ScanParts - Scanner v5 (Autodesk Fusion 360 design; units mm, degrees)
part number: 2026-11-14-11-23-10-393
part number: 2026-11-14-11-23-14-018
part number: 2026-11-14-11-23-14-713
part number: 2026-11-14-11-23-15-283
part number: 2026-11-14-11-23-16-065
part number: 2026-11-14-11-23-16-734
part number: 2026-11-14-11-23-24-762
part number: 2026-11-14-11-23-25-385
part number: 2026-11-14-11-23-25-910
part number: 2026-11-14-11-23-26-535
part number: 2026-11-14-11-23-27-518
part number: 2026-11-14-11-23-28-138
part number: 2026-11-14-11-23-28-822
part number: 2026-11-14-11-23-29-557
part number: 2026-11-14-11-23-30-858
part number: 2026-11-14-11-23-31-655
part number: 2026-11-14-11-23-33-125
part number: 2026-11-14-11-23-34-058
part number: 2026-11-14-11-24-18-527
part number: 2026-11-14-11-24-22-530
part number: 2026-11-14-11-24-37-352
part number: 2026-11-14-11-24-41-219
Autodesk Fusion 360 part; units mm, degrees
sketch "Esboço1" plane through (0, 0, 0) normal (0, 0, 1) x (1, 0, 0) in component "Pé de borracha Ø20×30"
  circle A0 centre (0, 0) radius 10
extrude "Extrusão1" add sketch "Esboço1" along normal blind 30 makes body 1 in component "Pé de borracha Ø20×30"
ref_plane "Plano de trabalho1" through (0, 0, 30) normal (0, 0, 1) x (1, 0, 0) in component "Base MDF"
sketch "Esboço1 (2)" plane through (0, 0, 30) normal (0, 0, 1) x (1, 0, 0) in component "Base MDF"
  line L0 (-130, -120) -> (130, -120)
  line L1 (130, -120) -> (130, 150)
  line L2 (130, 150) -> (-130, 150)
  line L3 (-130, 150) -> (-130, -120)
  circle A0 centre (0, 0) radius 6
extrude "Extrusão1'" add sketch "Esboço1 (2)" along normal blind 15 separate body makes body 2 in component "Base MDF"
ref_plane "Plano de trabalho2" through (0, 0, 30) normal (0, 0, 1) x (1, 0, 0) in component "Base MDF"
sketch "Esboço2" plane through (0, 0, 30) normal (0, 0, 1) x (1, 0, 0) in component "Base MDF"
  line L0 (-10.2, 94.8) -> (10.2, 94.8)
  line L1 (10.2, 94.8) -> (10.2, 115.2)
  line L2 (10.2, 115.2) -> (-10.2, 115.2)
  line L3 (-10.2, 115.2) -> (-10.2, 94.8)
extrude "Extrusão2" cut sketch "Esboço2" along normal blind 15 bodies 2 in component "Base MDF"
ref_plane "Plano de trabalho1" through (0, 0, 11) normal (0, 0, 1) x (1, 0, 0) in component "Motor de passo 28BYJ-48"
sketch "Esboço1 (3)" plane through (0, 0, 11) normal (0, 0, 1) x (1, 0, 0) in component "Motor de passo 28BYJ-48"
  circle A0 centre (0, -8) radius 14
extrude "Extrusão1''" add sketch "Esboço1 (3)" along normal blind 19 separate body makes body 3 in component "Motor de passo 28BYJ-48"
ref_plane "Plano de trabalho2" through (0, 0, 29) normal (0, 0, 1) x (1, 0, 0) in component "Motor de passo 28BYJ-48"
sketch "Esboço2 (2)" plane through (0, 0, 29) normal (0, 0, 1) x (1, 0, 0) in component "Motor de passo 28BYJ-48"
  line L0 (-3.5, -29) -> (3.5, -29)
  line L1 (3.5, -29) -> (3.5, 13)
  line L2 (3.5, 13) -> (-3.5, 13)
  line L3 (-3.5, 13) -> (-3.5, -29)
  circle A0 centre (0, -25.5) radius 2.1
  circle A1 centre (0, 9.5) radius 2.1
extrude "Extrusão2'" add sketch "Esboço2 (2)" along normal blind 1 separate body makes body 4 in component "Motor de passo 28BYJ-48"
ref_plane "Plano de trabalho3" through (0, 0, 30) normal (0, 0, 1) x (1, 0, 0) in component "Motor de passo 28BYJ-48"
sketch "Esboço3" plane through (0, 0, 30) normal (0, 0, 1) x (1, 0, 0) in component "Motor de passo 28BYJ-48"
  circle A0 centre (0, 0) radius 2.5
extrude "Extrusão3" add sketch "Esboço3" along normal blind 19 separate body makes body 5 in component "Motor de passo 28BYJ-48"
ref_plane "Plano de trabalho1" through (0, 0, 47) normal (0, 0, 1) x (1, 0, 0) in component "Prato giratório Ø180"
sketch "Esboço1 (4)" plane through (0, 0, 47) normal (0, 0, 1) x (1, 0, 0) in component "Prato giratório Ø180"
  circle A0 centre (0, 0) radius 90
extrude "Extrusão1'''" add sketch "Esboço1 (4)" along normal blind 4 separate body makes body 6 in component "Prato giratório Ø180"
ref_plane "Plano de trabalho2" through (0, 0, 47) normal (0, 0, 1) x (1, 0, 0) in component "Prato giratório Ø180"
sketch "Esboço2 (3)" plane through (0, 0, 47) normal (0, 0, 1) x (1, 0, 0) in component "Prato giratório Ø180"
  circle A0 centre (0, 0) radius 2.5
extrude "Extrusão4" cut sketch "Esboço2 (3)" along normal blind 2 bodies 5 in component "Motor de passo 28BYJ-48"
extrude "Extrusão2''" cut sketch "Esboço2 (3)" along normal blind 2 bodies 6 in component "Prato giratório Ø180"
ref_plane "Plano de trabalho1" through (0, 0, 51) normal (0, 0, 1) x (1, 0, 0) in component "Alvos de referência (24× a cada 15°)"
sketch "Esboço1 (5)" plane through (0, 0, 51) normal (0, 0, 1) x (1, 0, 0) in component "Alvos de referência (24× a cada 15°)"
  line L0 (76.5, -3.5) -> (83.5, -3.5)
  line L1 (83.5, -3.5) -> (83.5, 3.5)
  line L2 (83.5, 3.5) -> (76.5, 3.5)
  line L3 (76.5, 3.5) -> (76.5, -3.5)
  line L4 (74.7992, 16.4189) -> (81.5607, 18.2306)
  line L5 (81.5607, 18.2306) -> (79.7489, 24.9921)
  line L6 (79.7489, 24.9921) -> (72.9875, 23.1804)
  line L7 (72.9875, 23.1804) -> (74.7992, 16.4189)
  line L8 (68.0009, 35.2189) -> (74.0631, 38.7189)
  line L9 (74.0631, 38.7189) -> (70.5631, 44.7811)
  line L10 (70.5631, 44.7811) -> (64.5009, 41.2811)
  line L11 (64.5009, 41.2811) -> (68.0009, 35.2189)
  line L12 (56.5685, 51.6188) -> (61.5183, 56.5685)
  line L13 (61.5183, 56.5685) -> (56.5685, 61.5183)
  line L14 (56.5685, 61.5183) -> (51.6188, 56.5685)
  line L15 (51.6188, 56.5685) -> (56.5685, 51.6188)
  line L16 (41.2811, 64.5009) -> (44.7811, 70.5631)
  line L17 (44.7811, 70.5631) -> (38.7189, 74.0631)
  line L18 (38.7189, 74.0631) -> (35.2189, 68.0009)
  line L19 (35.2189, 68.0009) -> (41.2811, 64.5009)
  line L20 (23.1804, 72.9875) -> (24.9921, 79.7489)
  line L21 (24.9921, 79.7489) -> (18.2306, 81.5607)
  line L22 (18.2306, 81.5607) -> (16.4189, 74.7992)
  line L23 (16.4189, 74.7992) -> (23.1804, 72.9875)
  line L24 (3.5, 76.5) -> (3.5, 83.5)
  line L25 (3.5, 83.5) -> (-3.5, 83.5)
  line L26 (-3.5, 83.5) -> (-3.5, 76.5)
  line L27 (-3.5, 76.5) -> (3.5, 76.5)
  line L28 (-16.4189, 74.7992) -> (-18.2306, 81.5607)
  line L29 (-18.2306, 81.5607) -> (-24.9921, 79.7489)
  line L30 (-24.9921, 79.7489) -> (-23.1804, 72.9875)
  line L31 (-23.1804, 72.9875) -> (-16.4189, 74.7992)
  line L32 (-35.2189, 68.0009) -> (-38.7189, 74.0631)
  line L33 (-38.7189, 74.0631) -> (-44.7811, 70.5631)
  line L34 (-44.7811, 70.5631) -> (-41.2811, 64.5009)
  line L35 (-41.2811, 64.5009) -> (-35.2189, 68.0009)
  line L36 (-51.6188, 56.5685) -> (-56.5685, 61.5183)
  line L37 (-56.5685, 61.5183) -> (-61.5183, 56.5685)
  line L38 (-61.5183, 56.5685) -> (-56.5685, 51.6188)
  line L39 (-56.5685, 51.6188) -> (-51.6188, 56.5685)
  line L40 (-64.5009, 41.2811) -> (-70.5631, 44.7811)
  line L41 (-70.5631, 44.7811) -> (-74.0631, 38.7189)
  line L42 (-74.0631, 38.7189) -> (-68.0009, 35.2189)
  line L43 (-68.0009, 35.2189) -> (-64.5009, 41.2811)
  line L44 (-72.9875, 23.1804) -> (-79.7489, 24.9921)
  line L45 (-79.7489, 24.9921) -> (-81.5607, 18.2306)
  line L46 (-81.5607, 18.2306) -> (-74.7992, 16.4189)
  line L47 (-74.7992, 16.4189) -> (-72.9875, 23.1804)
  line L48 (-76.5, 3.5) -> (-83.5, 3.5)
  line L49 (-83.5, 3.5) -> (-83.5, -3.5)
  line L50 (-83.5, -3.5) -> (-76.5, -3.5)
  line L51 (-76.5, -3.5) -> (-76.5, 3.5)
  line L52 (-74.7992, -16.4189) -> (-81.5607, -18.2306)
  line L53 (-81.5607, -18.2306) -> (-79.7489, -24.9921)
  line L54 (-79.7489, -24.9921) -> (-72.9875, -23.1804)
  line L55 (-72.9875, -23.1804) -> (-74.7992, -16.4189)
  line L56 (-68.0009, -35.2189) -> (-74.0631, -38.7189)
  line L57 (-74.0631, -38.7189) -> (-70.5631, -44.7811)
  line L58 (-70.5631, -44.7811) -> (-64.5009, -41.2811)
  line L59 (-64.5009, -41.2811) -> (-68.0009, -35.2189)
  line L60 (-56.5685, -51.6188) -> (-61.5183, -56.5685)
  line L61 (-61.5183, -56.5685) -> (-56.5685, -61.5183)
  line L62 (-56.5685, -61.5183) -> (-51.6188, -56.5685)
  line L63 (-51.6188, -56.5685) -> (-56.5685, -51.6188)
  line L64 (-41.2811, -64.5009) -> (-44.7811, -70.5631)
  line L65 (-44.7811, -70.5631) -> (-38.7189, -74.0631)
  line L66 (-38.7189, -74.0631) -> (-35.2189, -68.0009)
  line L67 (-35.2189, -68.0009) -> (-41.2811, -64.5009)
  line L68 (-23.1804, -72.9875) -> (-24.9921, -79.7489)
  line L69 (-24.9921, -79.7489) -> (-18.2306, -81.5607)
  line L70 (-18.2306, -81.5607) -> (-16.4189, -74.7992)
  line L71 (-16.4189, -74.7992) -> (-23.1804, -72.9875)
  line L72 (-3.5, -76.5) -> (-3.5, -83.5)
  line L73 (-3.5, -83.5) -> (3.5, -83.5)
  line L74 (3.5, -83.5) -> (3.5, -76.5)
  line L75 (3.5, -76.5) -> (-3.5, -76.5)
  line L76 (16.4189, -74.7992) -> (18.2306, -81.5607)
  line L77 (18.2306, -81.5607) -> (24.9921, -79.7489)
  line L78 (24.9921, -79.7489) -> (23.1804, -72.9875)
  line L79 (23.1804, -72.9875) -> (16.4189, -74.7992)
  line L80 (35.2189, -68.0009) -> (38.7189, -74.0631)
  line L81 (38.7189, -74.0631) -> (44.7811, -70.5631)
  line L82 (44.7811, -70.5631) -> (41.2811, -64.5009)
  line L83 (41.2811, -64.5009) -> (35.2189, -68.0009)
  line L84 (51.6188, -56.5685) -> (56.5685, -61.5183)
  line L85 (56.5685, -61.5183) -> (61.5183, -56.5685)
  line L86 (61.5183, -56.5685) -> (56.5685, -51.6188)
  line L87 (56.5685, -51.6188) -> (51.6188, -56.5685)
  line L88 (64.5009, -41.2811) -> (70.5631, -44.7811)
  line L89 (70.5631, -44.7811) -> (74.0631, -38.7189)
  line L90 (74.0631, -38.7189) -> (68.0009, -35.2189)
  line L91 (68.0009, -35.2189) -> (64.5009, -41.2811)
  line L92 (72.9875, -23.1804) -> (79.7489, -24.9921)
  line L93 (79.7489, -24.9921) -> (81.5607, -18.2306)
  line L94 (81.5607, -18.2306) -> (74.7992, -16.4189)
  line L95 (74.7992, -16.4189) -> (72.9875, -23.1804)
extrude "Extrusão1''''" add sketch "Esboço1 (5)" along normal blind 0.3 separate body makes body 7 at (68.855, -38.4063, 51) makes body 8 at (41.5937, -69.7091, 51) makes body 9 at (-1.1667, -81.1667, 51) makes body 10 at (-40.427, -67.6883, 51) makes body 11 at (-69.7091, -41.5937, 51) makes body 12 at (-81.1667, 1.1667, 51) makes body 13 at (-78.099, 22.1344, 51) makes body 14 at (-58.2185, 56.5685, 51) makes body 15 at (-19.2767, 76.4491, 51) makes body 16 at (19.2767, 76.4491, 51) makes body 17 at (56.5685, 54.9186, 51) makes body 18 at (76.4491, 19.2767, 51) makes body 19 at (68.855, 38.4063, 51) makes body 20 at (40.427, 67.6883, 51) makes body 21 at (1.1667, 78.8333, 51) makes body 22 at (-38.4063, 68.855, 51) makes body 23 at (-69.7091, 41.5937, 51) makes body 24 at (78.8333, 1.1667, 51) makes body 25 at (-78.099, -22.1344, 51) makes body 26 at (-56.5685, -58.2185, 51) makes body 27 at (-22.1344, -78.099, 51) makes body 28 at (22.1344, -78.099, 51) makes body 29 at (54.9186, -56.5685, 51) makes body 30 at (78.099, -22.1344, 51) in component "Alvos de referência (24× a cada 15°)"
ref_plane "Plano de trabalho1" through (0, 0, 22) normal (0, 0, 1) x (1, 0, 0) in component "Flange da haste (sob a base)"
sketch "Esboço1 (6)" plane through (0, 0, 22) normal (0, 0, 1) x (1, 0, 0) in component "Flange da haste (sob a base)"
  line L0 (-25, 80) -> (25, 80)
  line L1 (25, 80) -> (25, 130)
  line L2 (25, 130) -> (-25, 130)
  line L3 (-25, 130) -> (-25, 80)
  circle A0 centre (-17, 88) radius 2.5
  circle A1 centre (-17, 122) radius 2.5
  circle A2 centre (17, 88) radius 2.5
  circle A3 centre (17, 122) radius 2.5
extrude "Extrusão1'''''" add sketch "Esboço1 (6)" along normal blind 8 separate body makes body 31 in component "Flange da haste (sob a base)"
ref_plane "Plano de trabalho1" through (0, 0, 30) normal (0, 0, 1) x (1, 0, 0) in component "Haste vertical 20x20 (175 mm)"
sketch "Esboço1 (7)" plane through (0, 0, 30) normal (0, 0, 1) x (1, 0, 0) in component "Haste vertical 20x20 (175 mm)"
  line L0 (-10, 95) -> (10, 95)
  line L1 (10, 95) -> (10, 115)
  line L2 (10, 115) -> (-10, 115)
  line L3 (-10, 115) -> (-10, 95)
  circle A0 centre (0, 105) radius 2.1
extrude "Extrusão1''''''" add sketch "Esboço1 (7)" along normal blind 175 separate body makes body 32 in component "Haste vertical 20x20 (175 mm)"
ref_plane "Plano de trabalho1" through (0, 0, 159) normal (0, 0, 1) x (1, 0, 0) in component "Carro de ajuste"
sketch "Esboço1 (8)" plane through (0, 0, 159) normal (0, 0, 1) x (1, 0, 0) in component "Carro de ajuste"
  line L0 (-20, 85) -> (20, 85)
  line L1 (20, 85) -> (20, 125)
  line L2 (20, 125) -> (-20, 125)
  line L3 (-20, 125) -> (-20, 85)
  line L4 (-10.2, 94.8) -> (10.2, 94.8)
  line L5 (10.2, 94.8) -> (10.2, 115.2)
  line L6 (10.2, 115.2) -> (-10.2, 115.2)
  line L7 (-10.2, 115.2) -> (-10.2, 94.8)
extrude "Extrusão1'''''''" add sketch "Esboço1 (8)" along normal blind 40 separate body makes body 33 in component "Carro de ajuste"
ref_plane "Plano de trabalho1" through (20, 0, 0) normal (1, 0, 0) x (0, 1, 0) in component "Manípulo"
sketch "Esboço1 (9)" plane through (20, 0, 0) normal (1, 0, 0) x (0, 0, -1) in component "Manípulo"
  circle A0 centre (-179, 105) radius 4
extrude "Extrusão1''''''''" add sketch "Esboço1 (9)" along normal blind 10 separate body makes body 34 in component "Manípulo"
ref_plane "Plano de trabalho2" through (30, 0, 0) normal (1, 0, 0) x (0, 1, 0) in component "Manípulo"
sketch "Esboço2 (4)" plane through (30, 0, 0) normal (1, 0, 0) x (0, 0, -1) in component "Manípulo"
  circle A0 centre (-179, 105) radius 11
extrude "Extrusão2'''" add sketch "Esboço2 (4)" along normal blind 8 separate body makes body 35 in component "Manípulo"
ref_plane "Plano de trabalho1" through (0, 0, 169) normal (0, 0, 1) x (1, 0, 0) in component "Braço 20x20 (55 mm)"
sketch "Esboço1 (10)" plane through (0, 0, 169) normal (0, 0, 1) x (1, 0, 0) in component "Braço 20x20 (55 mm)"
  line L0 (-10, 30) -> (10, 30)
  line L1 (10, 30) -> (10, 85)
  line L2 (10, 85) -> (-10, 85)
  line L3 (-10, 85) -> (-10, 30)
extrude "Extrusão1'''''''''" add sketch "Esboço1 (10)" along normal blind 20 separate body makes body 36 in component "Braço 20x20 (55 mm)"
ref_plane "Plano de trabalho1" through (0, 0, 164) normal (0, 0, 1) x (1, 0, 0) in component "Suporte câmera + LED Ø170"
sketch "Esboço1 (11)" plane through (0, 0, 164) normal (0, 0, 1) x (1, 0, 0) in component "Suporte câmera + LED Ø170"
  circle A0 centre (0, 0) radius 85
  circle A1 centre (0, 0) radius 8
extrude "Extrusão1''''''''''" add sketch "Esboço1 (11)" along normal blind 5 separate body makes body 37 in component "Suporte câmera + LED Ø170"
ref_plane "Plano de trabalho1" through (0, 0, 152) normal (0, 0, 1) x (1, 0, 0) in component "Ring light 6500K Ø160"
sketch "Esboço1 (12)" plane through (0, 0, 152) normal (0, 0, 1) x (1, 0, 0) in component "Ring light 6500K Ø160"
  circle A0 centre (0, 0) radius 80
  circle A1 centre (0, 0) radius 55
extrude "Extrusão1'''''''''''" add sketch "Esboço1 (12)" along normal blind 12 separate body makes body 38 in component "Ring light 6500K Ø160"
ref_plane "Plano de trabalho1" through (0, 0, 169) normal (0, 0, 1) x (1, 0, 0) in component "Câmera IMX219"
sketch "Esboço1 (13)" plane through (0, 0, 169) normal (0, 0, 1) x (1, 0, 0) in component "Câmera IMX219"
  line L0 (-12.5, -12) -> (12.5, -12)
  line L1 (12.5, -12) -> (12.5, 12)
  line L2 (12.5, 12) -> (-12.5, 12)
  line L3 (-12.5, 12) -> (-12.5, -12)
extrude "Extrusão1''''''''''''" add sketch "Esboço1 (13)" along normal blind 1.6 separate body makes body 39 in component "Câmera IMX219"
ref_plane "Plano de trabalho2" through (0, 0, 151) normal (0, 0, 1) x (1, 0, 0) in component "Câmera IMX219"
sketch "Esboço2 (5)" plane through (0, 0, 151) normal (0, 0, 1) x (1, 0, 0) in component "Câmera IMX219"
  circle A0 centre (0, 0) radius 7
extrude "Extrusão2''''" add sketch "Esboço2 (5)" along normal blind 18 separate body makes body 40 in component "Câmera IMX219"
ref_plane "Plano de trabalho1" through (0, 0, 148) normal (0, 0, 1) x (1, 0, 0) in component "Filtro polarizador CPL"
sketch "Esboço1 (14)" plane through (0, 0, 148) normal (0, 0, 1) x (1, 0, 0) in component "Filtro polarizador CPL"
  circle A0 centre (0, 0) radius 8
  circle A1 centre (0, 0) radius 5
extrude "Extrusão1'''''''''''''" add sketch "Esboço1 (14)" along normal blind 3 separate body makes body 41 in component "Filtro polarizador CPL"
ref_plane "Plano de trabalho1" through (0, 0, 169) normal (0, 0, 1) x (1, 0, 0) in component "Suporte do laser"
sketch "Esboço1 (15)" plane through (0, 0, 169) normal (0, 0, 1) x (1, 0, 0) in component "Suporte do laser"
  line L0 (10, -110) -> (16, -110)
  line L1 (16, -110) -> (16, -75)
  line L2 (16, -75) -> (10, -75)
  line L3 (10, -75) -> (10, -110)
extrude "Extrusão1''''''''''''''" add sketch "Esboço1 (15)" along normal blind 3 separate body makes body 42 in component "Suporte do laser"
ref_plane "Plano de trabalho2" through (0, 0, 138) normal (0, 0, 1) x (1, 0, 0) in component "Suporte do laser"
sketch "Esboço2 (6)" plane through (0, 0, 138) normal (0, 0, 1) x (1, 0, 0) in component "Suporte do laser"
  line L0 (10, -110) -> (16, -110)
  line L1 (16, -110) -> (16, -92)
  line L2 (16, -92) -> (10, -92)
  line L3 (10, -92) -> (10, -110)
extrude "Extrusão2'''''" add sketch "Esboço2 (6)" along normal blind 31 separate body makes body 43 in component "Suporte do laser"
ref_plane "Plano de trabalho1" through (0, 0, -7) normal (0, 0, 1) x (1, 0, 0) in component "Abraçadeira do laser"
sketch "Esboço1 (16)" plane through (0, 0, -7) normal (0, 0, 1) x (1, 0, 0) in component "Abraçadeira do laser"
  circle A0 centre (0, 0) radius 10
  circle A1 centre (0, 0) radius 6
extrude "Extrusão1'''''''''''''''" add sketch "Esboço1 (16)" along normal blind 14 separate body makes body 44 in component "Abraçadeira do laser"
ref_plane "Plano de trabalho1" through (0, 0, -15) normal (0, 0, 1) x (1, 0, 0) in component "Laser de linha 650 nm Ø12"
sketch "Esboço1 (17)" plane through (0, 0, -15) normal (0, 0, 1) x (1, 0, 0) in component "Laser de linha 650 nm Ø12"
  circle A0 centre (0, 0) radius 6
extrude "Extrusão1''''''''''''''''" add sketch "Esboço1 (17)" along normal blind 30 separate body makes body 45 in component "Laser de linha 650 nm Ø12"
ref_plane "Plano de trabalho2" through (0, 0, -16) normal (0, 0, 1) x (1, 0, 0) in component "Laser de linha 650 nm Ø12"
sketch "Esboço2 (7)" plane through (0, 0, -16) normal (0, 0, 1) x (1, 0, 0) in component "Laser de linha 650 nm Ø12"
  circle A0 centre (0, 0) radius 3
extrude "Extrusão2''''''" add sketch "Esboço2 (7)" along normal blind 1 separate body makes body 46 in component "Laser de linha 650 nm Ø12"
ref_plane "Plano de trabalho1" through (0, 0, 196) normal (0, 0, 1) x (1, 0, 0) in component "Plataforma do Jetson"
sketch "Esboço1 (18)" plane through (0, 0, 196) normal (0, 0, 1) x (1, 0, 0) in component "Plataforma do Jetson"
  line L0 (-58, -8) -> (37, -8)
  line L1 (37, -8) -> (37, 83)
  line L2 (37, 83) -> (-58, 83)
  line L3 (-58, 83) -> (-58, -8)
extrude "Extrusão1'''''''''''''''''" add sketch "Esboço1 (18)" along normal blind 4 separate body makes body 47 in component "Plataforma do Jetson"
ref_plane "Plano de trabalho2" through (0, 0, 189) normal (0, 0, 1) x (1, 0, 0) in component "Plataforma do Jetson"
sketch "Esboço2 (8)" plane through (0, 0, 189) normal (0, 0, 1) x (1, 0, 0) in component "Plataforma do Jetson"
  line L0 (-10, 45) -> (10, 45)
  line L1 (10, 45) -> (10, 57)
  line L2 (10, 57) -> (-10, 57)
  line L3 (-10, 57) -> (-10, 45)
extrude "Extrusão2'''''''" add sketch "Esboço2 (8)" along normal blind 7 separate body makes body 48 in component "Plataforma do Jetson"
ref_plane "Plano de trabalho3" through (0, 0, 189) normal (0, 0, 1) x (1, 0, 0) in component "Plataforma do Jetson"
sketch "Esboço3 (2)" plane through (0, 0, 189) normal (0, 0, 1) x (1, 0, 0) in component "Plataforma do Jetson"
  line L0 (-10, 70) -> (10, 70)
  line L1 (10, 70) -> (10, 82)
  line L2 (10, 82) -> (-10, 82)
  line L3 (-10, 82) -> (-10, 70)
extrude "Extrusão3'" add sketch "Esboço3 (2)" along normal blind 7 separate body makes body 49 in component "Plataforma do Jetson"
ref_plane "Plano de trabalho4" through (0, 0, 169) normal (0, 0, 1) x (1, 0, 0) in component "Plataforma do Jetson"
sketch "Esboço4" plane through (0, 0, 169) normal (0, 0, 1) x (1, 0, 0) in component "Plataforma do Jetson"
  circle A0 centre (-45, 5) radius 4
extrude "Extrusão4'" add sketch "Esboço4" along normal blind 27 separate body makes body 50 in component "Plataforma do Jetson"
ref_plane "Plano de trabalho5" through (0, 0, 169) normal (0, 0, 1) x (1, 0, 0) in component "Plataforma do Jetson"
sketch "Esboço5" plane through (0, 0, 169) normal (0, 0, 1) x (1, 0, 0) in component "Plataforma do Jetson"
  circle A0 centre (28, 5) radius 4
extrude "Extrusão5" add sketch "Esboço5" along normal blind 27 separate body makes body 51 in component "Plataforma do Jetson"
sketch "Esboço1 (19)" plane through (0, 0, 0) normal (0, 0, 1) x (1, 0, 0) in component "Jetson Orin Nano Dev Kit"
  line L0 (0, 0) -> (103, 0)
  line L1 (103, 0) -> (103, 90.5)
  line L2 (103, 90.5) -> (0, 90.5)
  line L3 (0, 90.5) -> (0, 0)
extrude "Extrusão1''''''''''''''''''" add sketch "Esboço1 (19)" along normal blind 6 separate body makes body 52 in component "Jetson Orin Nano Dev Kit"
ref_plane "Plano de trabalho1" through (0, 0, 6) normal (0, 0, 1) x (1, 0, 0) in component "Jetson Orin Nano Dev Kit"
sketch "Esboço2 (9)" plane through (0, 0, 6) normal (0, 0, 1) x (1, 0, 0) in component "Jetson Orin Nano Dev Kit"
  line L0 (1.5, 2) -> (101.5, 2)
  line L1 (101.5, 2) -> (101.5, 81)
  line L2 (101.5, 81) -> (1.5, 81)
  line L3 (1.5, 81) -> (1.5, 2)
  circle A0 centre (5.3, 77) radius 1.35
  circle A1 centre (96.8, 77) radius 1.35
  circle A2 centre (5.3, 18.3) radius 1.35
  circle A3 centre (96.8, 18.3) radius 1.35
extrude "Extrusão2''''''''" add sketch "Esboço2 (9)" along normal blind 1.57 separate body makes body 53 in component "Jetson Orin Nano Dev Kit"
ref_plane "Plano de trabalho2" through (0, 0, 10.97) normal (0, 0, 1) x (1, 0, 0) in component "Jetson Orin Nano Dev Kit"
sketch "Esboço3 (3)" plane through (0, 0, 10.97) normal (0, 0, 1) x (1, 0, 0) in component "Jetson Orin Nano Dev Kit"
  line L0 (15, 36) -> (84.6, 36)
  line L1 (84.6, 36) -> (84.6, 81)
  line L2 (84.6, 81) -> (15, 81)
  line L3 (15, 81) -> (15, 36)
extrude "Extrusão3''" add sketch "Esboço3 (3)" along normal blind 1 separate body makes body 54 in component "Jetson Orin Nano Dev Kit"
ref_plane "Plano de trabalho3" through (0, 0, 11.97) normal (0, 0, 1) x (1, 0, 0) in component "Jetson Orin Nano Dev Kit"
sketch "Esboço4 (2)" plane through (0, 0, 11.97) normal (0, 0, 1) x (1, 0, 0) in component "Jetson Orin Nano Dev Kit"
  line L0 (20.5, 40.9) -> (79, 40.9)
  line L1 (79, 40.9) -> (79, 80.2)
  line L2 (79, 80.2) -> (20.5, 80.2)
  line L3 (20.5, 80.2) -> (20.5, 40.9)
extrude "Extrusão4''" add sketch "Esboço4 (2)" along normal blind 22.8 separate body makes body 55 in component "Jetson Orin Nano Dev Kit"
ref_plane "Plano de trabalho4" through (0, 0, 34.77) normal (0, 0, 1) x (1, 0, 0) in component "Jetson Orin Nano Dev Kit"
sketch "Esboço5 (2)" plane through (0, 0, 34.77) normal (0, 0, 1) x (1, 0, 0) in component "Jetson Orin Nano Dev Kit"
  circle A0 centre (49.4, 60.6) radius 18
extrude "Extrusão5'" cut sketch "Esboço5 (2)" against normal blind 2 bodies 55 in component "Jetson Orin Nano Dev Kit"
ref_plane "Plano de trabalho5" through (0, 0, 32.77) normal (0, 0, 1) x (1, 0, 0) in component "Jetson Orin Nano Dev Kit"
sketch "Esboço6" plane through (0, 0, 32.77) normal (0, 0, 1) x (1, 0, 0) in component "Jetson Orin Nano Dev Kit"
  circle A0 centre (49.4, 60.6) radius 7
extrude "Extrusão6" add sketch "Esboço6" along normal blind 2 separate body makes body 56 in component "Jetson Orin Nano Dev Kit"
ref_plane "Plano de trabalho6" through (0, 0, 7.57) normal (0, 0, 1) x (1, 0, 0) in component "Jetson Orin Nano Dev Kit"
sketch "Esboço7" plane through (0, 0, 7.57) normal (0, 0, 1) x (1, 0, 0) in component "Jetson Orin Nano Dev Kit"
  line L0 (2.7, 0) -> (12, 0)
  line L1 (12, 0) -> (12, 14)
  line L2 (12, 14) -> (2.7, 14)
  line L3 (2.7, 14) -> (2.7, 0)
extrude "Extrusão7" add sketch "Esboço7" along normal blind 11 separate body makes body 57 in component "Jetson Orin Nano Dev Kit"
ref_plane "Plano de trabalho7" through (0, 0, 7.57) normal (0, 0, 1) x (1, 0, 0) in component "Jetson Orin Nano Dev Kit"
sketch "Esboço8" plane through (0, 0, 7.57) normal (0, 0, 1) x (1, 0, 0) in component "Jetson Orin Nano Dev Kit"
  line L0 (15.2, 0) -> (32.6, 0)
  line L1 (32.6, 0) -> (32.6, 15)
  line L2 (32.6, 15) -> (15.2, 15)
  line L3 (15.2, 15) -> (15.2, 0)
extrude "Extrusão8" add sketch "Esboço8" along normal blind 8.5 separate body makes body 58 in component "Jetson Orin Nano Dev Kit"
ref_plane "Plano de trabalho8" through (0, 0, 7.57) normal (0, 0, 1) x (1, 0, 0) in component "Jetson Orin Nano Dev Kit"
sketch "Esboço9" plane through (0, 0, 7.57) normal (0, 0, 1) x (1, 0, 0) in component "Jetson Orin Nano Dev Kit"
  line L0 (36.9, 0) -> (51.2, 0)
  line L1 (51.2, 0) -> (51.2, 17.5)
  line L2 (51.2, 17.5) -> (36.9, 17.5)
  line L3 (36.9, 17.5) -> (36.9, 0)
extrude "Extrusão9" add sketch "Esboço9" along normal blind 16.5 separate body makes body 59 in component "Jetson Orin Nano Dev Kit"
ref_plane "Plano de trabalho9" through (0, 0, 7.57) normal (0, 0, 1) x (1, 0, 0) in component "Jetson Orin Nano Dev Kit"
sketch "Esboço10" plane through (0, 0, 7.57) normal (0, 0, 1) x (1, 0, 0) in component "Jetson Orin Nano Dev Kit"
  line L0 (53.8, 0) -> (68.1, 0)
  line L1 (68.1, 0) -> (68.1, 17.5)
  line L2 (68.1, 17.5) -> (53.8, 17.5)
  line L3 (53.8, 17.5) -> (53.8, 0)
extrude "Extrusão10" add sketch "Esboço10" along normal blind 16.5 separate body makes body 60 in component "Jetson Orin Nano Dev Kit"
ref_plane "Plano de trabalho10" through (0, 0, 7.57) normal (0, 0, 1) x (1, 0, 0) in component "Jetson Orin Nano Dev Kit"
sketch "Esboço11" plane through (0, 0, 7.57) normal (0, 0, 1) x (1, 0, 0) in component "Jetson Orin Nano Dev Kit"
  line L0 (70.4, 0) -> (86.5, 0)
  line L1 (86.5, 0) -> (86.5, 21)
  line L2 (86.5, 21) -> (70.4, 21)
  line L3 (70.4, 21) -> (70.4, 0)
extrude "Extrusão11" add sketch "Esboço11" along normal blind 13.5 separate body makes body 61 in component "Jetson Orin Nano Dev Kit"
ref_plane "Plano de trabalho11" through (0, 0, 7.57) normal (0, 0, 1) x (1, 0, 0) in component "Jetson Orin Nano Dev Kit"
sketch "Esboço12" plane through (0, 0, 7.57) normal (0, 0, 1) x (1, 0, 0) in component "Jetson Orin Nano Dev Kit"
  line L0 (89, 0) -> (99.8, 0)
  line L1 (99.8, 0) -> (99.8, 7.5)
  line L2 (99.8, 7.5) -> (89, 7.5)
  line L3 (89, 7.5) -> (89, 0)
extrude "Extrusão12" add sketch "Esboço12" along normal blind 3.5 separate body makes body 62 in component "Jetson Orin Nano Dev Kit"
ref_plane "Plano de trabalho12" through (0, 0, 7.57) normal (0, 0, 1) x (1, 0, 0) in component "Jetson Orin Nano Dev Kit"
sketch "Esboço13" plane through (0, 0, 7.57) normal (0, 0, 1) x (1, 0, 0) in component "Jetson Orin Nano Dev Kit"
  line L0 (95.4, 22.2) -> (100.7, 22.2)
  line L1 (100.7, 22.2) -> (100.7, 73)
  line L2 (100.7, 73) -> (95.4, 73)
  line L3 (95.4, 73) -> (95.4, 22.2)
extrude "Extrusão13" add sketch "Esboço13" along normal blind 8.5 separate body makes body 63 in component "Jetson Orin Nano Dev Kit"
ref_plane "Plano de trabalho13" through (0, 0, 7.57) normal (0, 0, 1) x (1, 0, 0) in component "Jetson Orin Nano Dev Kit"
sketch "Esboço14" plane through (0, 0, 7.57) normal (0, 0, 1) x (1, 0, 0) in component "Jetson Orin Nano Dev Kit"
  line L0 (1.4, 51.6) -> (6.2, 51.6)
  line L1 (6.2, 51.6) -> (6.2, 68.6)
  line L2 (6.2, 68.6) -> (1.4, 68.6)
  line L3 (1.4, 68.6) -> (1.4, 51.6)
extrude "Extrusão14" add sketch "Esboço14" along normal blind 2.5 separate body makes body 64 in component "Jetson Orin Nano Dev Kit"
ref_plane "Plano de trabalho14" through (0, 0, 7.57) normal (0, 0, 1) x (1, 0, 0) in component "Jetson Orin Nano Dev Kit"
sketch "Esboço15" plane through (0, 0, 7.57) normal (0, 0, 1) x (1, 0, 0) in component "Jetson Orin Nano Dev Kit"
  line L0 (1.4, 26.7) -> (6.2, 26.7)
  line L1 (6.2, 26.7) -> (6.2, 42.7)
  line L2 (6.2, 42.7) -> (1.4, 42.7)
  line L3 (1.4, 42.7) -> (1.4, 26.7)
extrude "Extrusão15" add sketch "Esboço15" along normal blind 2.5 separate body makes body 65 in component "Jetson Orin Nano Dev Kit"
ref_plane "Plano de trabalho1" through (0, 0, 170.6) normal (0, 0, 1) x (1, 0, 0) in component "Cabo flat da câmera 22 vias"
sketch "Esboço1 (20)" plane through (0, 0, 170.6) normal (0, 0, 1) x (1, 0, 0) in component "Cabo flat da câmera 22 vias"
  line L0 (-6, -12.6) -> (6, -12.6)
  line L1 (6, -12.6) -> (6, -8)
  line L2 (6, -8) -> (-6, -8)
  line L3 (-6, -8) -> (-6, -12.6)
extrude "Extrusão1'''''''''''''''''''" add sketch "Esboço1 (20)" along normal blind 0.3 separate body makes body 66 in component "Cabo flat da câmera 22 vias"
ref_plane "Plano de trabalho2" through (0, 0, 170.6) normal (0, 0, 1) x (1, 0, 0) in component "Cabo flat da câmera 22 vias"
sketch "Esboço2 (10)" plane through (0, 0, 170.6) normal (0, 0, 1) x (1, 0, 0) in component "Cabo flat da câmera 22 vias"
  line L0 (-6, -12.6) -> (6, -12.6)
  line L1 (6, -12.6) -> (6, -12.3)
  line L2 (6, -12.3) -> (-6, -12.3)
  line L3 (-6, -12.3) -> (-6, -12.6)
extrude "Extrusão2'''''''''" add sketch "Esboço2 (10)" along normal blind 39.82 separate body makes body 67 in component "Cabo flat da câmera 22 vias"
ref_plane "Plano de trabalho3" through (0, 0, 210.12) normal (0, 0, 1) x (1, 0, 0) in component "Cabo flat da câmera 22 vias"
sketch "Esboço3 (4)" plane through (0, 0, 210.12) normal (0, 0, 1) x (1, 0, 0) in component "Cabo flat da câmera 22 vias"
  line L0 (-6, -12.6) -> (6, -12.6)
  line L1 (6, -12.6) -> (6, -7)
  line L2 (6, -7) -> (-6, -7)
  line L3 (-6, -7) -> (-6, -12.6)
extrude "Extrusão3'''" add sketch "Esboço3 (4)" along normal blind 0.3 separate body makes body 68 in component "Cabo flat da câmera 22 vias"
sketch "Esboço1 (21)" plane through (0, 0, 0) normal (0, 0, 1) x (1, 0, 0) in component "Driver ULN2003"
  circle A0 centre (3, 3) radius 2.5
extrude "Extrusão1''''''''''''''''''''" add sketch "Esboço1 (21)" along normal blind 3 separate body makes body 69 in component "Driver ULN2003"
sketch "Esboço2 (11)" plane through (0, 0, 0) normal (0, 0, 1) x (1, 0, 0) in component "Driver ULN2003"
  circle A0 centre (29, 3) radius 2.5
extrude "Extrusão2''''''''''" add sketch "Esboço2 (11)" along normal blind 3 separate body makes body 70 in component "Driver ULN2003"
sketch "Esboço3 (5)" plane through (0, 0, 0) normal (0, 0, 1) x (1, 0, 0) in component "Driver ULN2003"
  circle A0 centre (3, 32) radius 2.5
extrude "Extrusão3''''" add sketch "Esboço3 (5)" along normal blind 3 separate body makes body 71 in component "Driver ULN2003"
sketch "Esboço4 (3)" plane through (0, 0, 0) normal (0, 0, 1) x (1, 0, 0) in component "Driver ULN2003"
  circle A0 centre (29, 32) radius 2.5
extrude "Extrusão4'''" add sketch "Esboço4 (3)" along normal blind 3 separate body makes body 72 in component "Driver ULN2003"
ref_plane "Plano de trabalho1" through (0, 0, 3) normal (0, 0, 1) x (1, 0, 0) in component "Driver ULN2003"
sketch "Esboço5 (3)" plane through (0, 0, 3) normal (0, 0, 1) x (1, 0, 0) in component "Driver ULN2003"
  line L0 (0, 0) -> (32, 0)
  line L1 (32, 0) -> (32, 35)
  line L2 (32, 35) -> (0, 35)
  line L3 (0, 35) -> (0, 0)
extrude "Extrusão5''" add sketch "Esboço5 (3)" along normal blind 1.6 separate body makes body 73 in component "Driver ULN2003"
ref_plane "Plano de trabalho2" through (0, 0, 4.6) normal (0, 0, 1) x (1, 0, 0) in component "Driver ULN2003"
sketch "Esboço6 (2)" plane through (0, 0, 4.6) normal (0, 0, 1) x (1, 0, 0) in component "Driver ULN2003"
  line L0 (6, 8) -> (26, 8)
  line L1 (26, 8) -> (26, 15)
  line L2 (26, 15) -> (6, 15)
  line L3 (6, 15) -> (6, 8)
extrude "Extrusão6'" add sketch "Esboço6 (2)" along normal blind 4 separate body makes body 74 in component "Driver ULN2003"
ref_plane "Plano de trabalho3" through (0, 0, 4.6) normal (0, 0, 1) x (1, 0, 0) in component "Driver ULN2003"
sketch "Esboço7 (2)" plane through (0, 0, 4.6) normal (0, 0, 1) x (1, 0, 0) in component "Driver ULN2003"
  line L0 (9, 24) -> (23, 24)
  line L1 (23, 24) -> (23, 30)
  line L2 (23, 30) -> (9, 30)
  line L3 (9, 30) -> (9, 24)
extrude "Extrusão7'" add sketch "Esboço7 (2)" along normal blind 7 separate body makes body 75 in component "Driver ULN2003"
component "Pé de borracha Ø20×30" placed x (1, 0, 0) y (0, 1, 0) z (0, 0, 1) at (110, -100, 0)
component "Pé de borracha Ø20×30" placed x (1, 0, 0) y (0, 1, 0) z (0, 0, 1) at (-110, -100, 0)
component "Pé de borracha Ø20×30" placed x (1, 0, 0) y (0, 1, 0) z (0, 0, 1) at (110, 130, 0)
component "Pé de borracha Ø20×30" placed x (1, 0, 0) y (0, 1, 0) z (0, 0, 1) at (-110, 130, 0)
component "Base MDF" placed x (1, 0, 0) y (0, 1, 0) z (0, 0, 1) at (0, 0, 0)
component "Motor de passo 28BYJ-48" placed x (1, 0, 0) y (0, 1, 0) z (0, 0, 1) at (0, 0, 0)
component "Prato giratório Ø180" placed x (1, 0, 0) y (0, 1, 0) z (0, 0, 1) at (0, 0, 0)
component "Alvos de referência (24× a cada 15°)" placed x (1, 0, 0) y (0, 1, 0) z (0, 0, 1) at (0, 0, 0)
component "Flange da haste (sob a base)" placed x (1, 0, 0) y (0, 1, 0) z (0, 0, 1) at (0, 0, 0)
component "Haste vertical 20x20 (175 mm)" placed x (1, 0, 0) y (0, 1, 0) z (0, 0, 1) at (0, 0, 0)
component "Carro de ajuste" placed x (1, 0, 0) y (0, 1, 0) z (0, 0, 1) at (0, 0, 0)
component "Manípulo" placed x (1, 0, 0) y (0, 1, 0) z (0, 0, 1) at (0, 0, 0)
component "Braço 20x20 (55 mm)" placed x (1, 0, 0) y (0, 1, 0) z (0, 0, 1) at (0, 0, 0)
component "Suporte câmera + LED Ø170" placed x (1, 0, 0) y (0, 1, 0) z (0, 0, 1) at (0, 0, 0)
component "Ring light 6500K Ø160" placed x (1, 0, 0) y (0, 1, 0) z (0, 0, 1) at (0, 0, 0)
component "Câmera IMX219" placed x (1, 0, 0) y (0, 1, 0) z (0, 0, 1) at (0, 0, 0)
component "Filtro polarizador CPL" placed x (1, 0, 0) y (0, 1, 0) z (0, 0, 1) at (0, 0, 0)
component "Suporte do laser" placed x (1, 0, 0) y (0, 1, 0) z (0, 0, 1) at (0, 0, 0)
component "Abraçadeira do laser" placed x (1, 0, 0) y (0, 0.703545, 0.710651) z (0, -0.710651, 0.703545) at (0, -100, 150)
component "Laser de linha 650 nm Ø12" placed x (1, 0, 0) y (0, 0.703545, 0.710651) z (0, -0.710651, 0.703545) at (0, -100, 150)
component "Plataforma do Jetson" placed x (1, 0, 0) y (0, 1, 0) z (0, 0, 1) at (0, 0, 0)
component "Jetson Orin Nano Dev Kit" placed x (0, 1, 0) y (-1, 0, 0) z (0, 0, 1) at (34.7, -12, 200)
component "Cabo flat da câmera 22 vias" placed x (1, 0, 0) y (0, 1, 0) z (0, 0, 1) at (0, 0, 0)
component "Driver ULN2003" placed x (1, 0, 0) y (0, 1, 0) z (0, 0, 1) at (90, -110, 45)
named bodies: "Base MDF", "Corpo", "Orelhas", "Eixo", "Prato", "Alvo 1", "Alvo 2", "Alvo 3", "Alvo 4", "Alvo 5", "Alvo 6", "Alvo 7", "Alvo 8", "Alvo 9", "Alvo 10", "Alvo 11", "Alvo 12", "Alvo 13", "Alvo 14", "Alvo 15", "Alvo 16", "Alvo 17", "Alvo 18", "Alvo 19", "Alvo 20", "Alvo 21", "Alvo 22", "Alvo 23", "Alvo 24", "Flange", "Haste", "Carro", "Cabeça", "Braço", "Suporte", "Ring light", "Placa", "Lente", "Filtro", "Aba", "Abraçadeira", "Laser", "Janela", "Plataforma", "Calço 1", "Calço 2", "Coluna de apoio 1", "Coluna de apoio 2", "Suporte (base)", "Placa carrier", "Módulo SO-DIMM", "Dissipador", "Hub da ventoinha", "Conector DC", "DisplayPort", "USB-A J6", "USB-A J7", "RJ45", "USB-C", "Header 40 pinos", "Conector câmera J20", "Conector câmera J21", "Trecho inferior", "Trecho vertical", "Trecho superior", "Espaçador 1", "Espaçador 2", "Espaçador 3", "Espaçador 4", "CI ULN2003", "Conector do motor"
